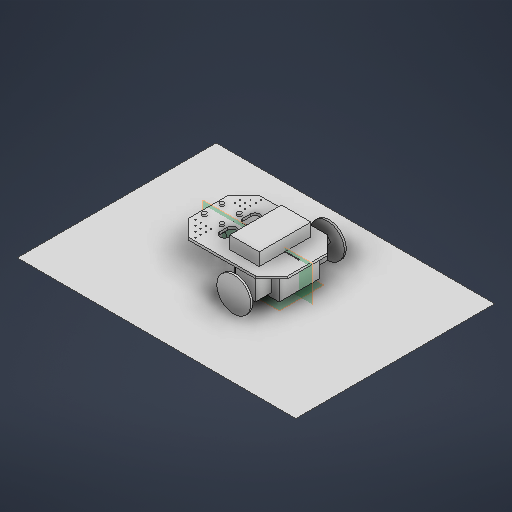
# Autodesk Inventor part: Part1
Saved by Autodesk Inventor 2027.1 (Build 311270010, 270A)
## iProperties
Created: 2026-10-01
Part Number: Part1
Material: Generic
Document SubType Name: Modeling
Designer: valde
Density: 1 g/cm^3
Appearance: Default
Author: valde
Autodesk Inventor part; units mm, degrees
ref_plane "YZ Plane" through (0, 0, 0) normal (1, 0, 0) x (0, 1, 0)
ref_plane "XZ Plane" through (0, 0, 0) normal (0, 1, 0) x (-1, 0, 0)
ref_plane "XY Plane" through (0, 0, 0) normal (0, 0, 1) x (1, 0, 0)
sketch "Sketch1" plane through (0, 0, 0) normal (0, 1, 0) x (-1, 0, 0)
  line L0 (0, 0) -> (-250, 0)
  line L1 (-250, 0) -> (-250, -180)
  line L2 (-250, -180) -> (0, -180)
  line L3 (0, -180) -> (0, 0)
  line L4 (0, -180) -> (0, -140)
  line L5 (0, -180) -> (-40, -180)
  line L6 (-40, -180) -> (0, -140)
  line L7 (0, 0) -> (0, -40)
  line L8 (0, -40) -> (-40, 0)
  line L9 (0, 0) -> (-40, 0)
  line L10 (-125, -180) -> (-125, 0)
  line L11 (0, 0) -> (0, -40)
  line L12 (-40, 0) -> (0, 0)
  line L13 (-210, -180) -> (-250, -140)
  line L14 (-250, -40) -> (-210, 0)
  dimension "d0" = 250
  dimension "d1" = 180
  dimension "d2" = 40
  dimension "d3" = 40
  dimension "d4" = 40
  constraints: 30 end point, 4 point on line, 4 symmetric about line, 3 perpendicular, 2 collinear, 2 midpoint, 2 parallel, 1 horizontal
  measures "d0" distance of L2.end L1.end
  measures "d1" distance of L1.end L0.end
  measures "d2" distance of L2.end L4.end
  measures "d3" distance of L2.end L5.end
  measures "d4" distance of L0.start L7.end
extrude "Extrusion1" add sketch "Sketch1" along normal blind 6 contours L8 L3 L6 L2 L10 L0 | L10 L2 L13 L1 L14 L0
sketch "Sketch8" plane through (0, 0, 0) normal (0, -1, 0) x (1, 0, 0)
  line L0 (250, -40) -> (250, -140) projected
  line L1 (210, 0) -> (250, -40) projected
  line L2 (164, -39) -> (160, -39) projected
  line L3 (210, 0) -> (160, 0)
  line L4 (160, 0) -> (160, -39)
  line L5 (160, -39) -> (210, -39)
  line L6 (210, -39) -> (210, 0)
  line L7 (250, -90) -> (0, -90)
  line L8 (0, -140) -> (0, -40) projected
  line L9 (164, -141) -> (160, -141)
  line L10 (210, -180) -> (160, -180)
  line L11 (160, -180) -> (160, -141)
  line L12 (160, -141) -> (210, -141)
  line L13 (210, -141) -> (210, -180)
  point P0 (0, 0)
  constraints: 20 end point, 5 symmetric about line, 2 midpoint, 2 parallel, 1 horizontal, 1 perpendicular
extrude "Extrusion7" add sketch "Sketch8" along normal blind 50 separate body
sketch "Sketch9" plane through (160, 0, 0) normal (0, 0, 1) x (1, 0, 0)
  line L0 (50, 0) -> (-120, 0) projected
  line L1 (0, 0) -> (0, -50) projected
  line L2 (50, 0) -> (0, 0)
  line L3 (0, 0) -> (25, 0)
  line L4 (25, 0) -> (25, -24)
  line L5 (25, 0) -> (49, 0) construction
  line L6 (25, -24) -> (25, -39)
  circle A0 centre (25, -31.5) radius 7.5
  point P0 (-160, 0)
  dimension "d39" = 24
  dimension "d40" = 90
  dimension "d41" = 15
  constraints: 10 end point, 3 perpendicular, 2 midpoint, 1 horizontal, 1 vertical, 1 vertical alignment, 2 other
  measures "d39" distance of L3.end L4.end
  measures "d40" angle of L4 L5
  measures "d41" distance of L4.end L6.end
extrude "Extrusion8" add sketch "Sketch9" along normal blind 30 separate body
sketch "Sketch10" plane through (185, -31.5, 30) normal (0, 0, 1) x (1, 0, 0)
  circle A0 centre (0, 0) radius 42.5
  point P0 (-185, 31.5)
  dimension "d44" = 85
  constraints: 1 centre point
  measures "d44" diameter of A0
extrude "Extrusion9" add sketch "Sketch10" against normal blind 5 bodies 3
sketch "Sketch11" plane through (0, 6, 0) normal (0, 1, 0) x (1, 0, 0)
  line L0 (250, 40) -> (250, 140) projected
  line L1 (250, 90) -> (229, 90)
  line L2 (229, 90) -> (144, 90)
  circle A0 centre (229, 90) radius 1
  circle A1 centre (144, 90) radius 1
  line L3 (144, 89) -> (229, 89)
  line L4 (229, 91) -> (144, 91)
  line L5 (229, 90) -> (189, 90)
  line L6 (229, 90) -> (269, 90) construction
  line L7 (189, 90) -> (189, 100)
  line L8 (189, 100) -> (104, 100)
  circle A2 centre (104, 100) radius 1
  circle A3 centre (189, 100) radius 1
  line L9 (189, 99) -> (104, 99)
  line L10 (104, 101) -> (189, 101)
  line L11 (189, 90) -> (189, 80)
  line L12 (189, 80) -> (104, 80)
  circle A4 centre (104, 80) radius 1
  circle A5 centre (189, 80) radius 1
  line L13 (189, 81) -> (104, 81)
  line L14 (104, 79) -> (189, 79)
  line L15 (0, 140) -> (0, 40) projected
  line L16 (0, 51.6193) -> (80, 51.6193)
  line L17 (0, 51.6193) -> (80, 51.6193) construction
  line L18 (40, 0) -> (210, 0) projected
  line L19 (80, 0) -> (80, 40)
  line L20 (80, 0) -> (120, 0) construction
  circle A6 centre (80, 51.6193) radius 11.6193
  line L21 (80, 40) -> (80, 82)
  line L22 (80, 82) -> (80, 70.381)
  circle A7 centre (80, 70.381) radius 11.619
  line L23 (68.3807, 51.6193) -> (68.381, 70.3812)
  line L24 (91.6193, 51.6193) -> (91.619, 70.3812)
  circle A8 centre (80, 128.3807) radius 11.6193
  circle A9 centre (80, 109.619) radius 11.619
  line L25 (68.3807, 128.3807) -> (68.381, 109.6188)
  line L26 (91.6193, 128.3807) -> (91.619, 109.6188)
  point P0 (0, 0)
  point P1 (91.619, 109.619)
  point P2 (91.619, 70.381)
  dimension "d47" = 21
  dimension "d48" = 85
  dimension "d49" = 2
  dimension "d50" = 2
  dimension "d51" = 40
  dimension "d52" = 180
  dimension "d53" = 10
  dimension "d54" = 85
  dimension "d55" = 90
  dimension "d56" = 2
  dimension "d57" = 2
  dimension "d58" = 80
  dimension "d59" = 0
  dimension "d60" = 40
  dimension "d61" = 90
  dimension "d62" = 42
  dimension "d63" = 11.619
  constraints: 48 end point, 24 point on circle, 15 symmetric about line, 10 centre point, 8 coincident, 7 point on line, 7 tangent, 4 horizontal, 4 perpendicular, 3 equal length, 1 collinear, 1 midpoint, 1 vertical, 4 other
  measures "d47" distance of L1.start L1.end
  measures "d48" distance of L1.end L2.end
  measures "d49" diameter of A0
  measures "d50" diameter of A1
  measures "d51" distance of L5.start L5.end
  measures "d52" angle of L5 L6
  measures "d53" distance of L5.end L7.end
  measures "d54" distance of L7.end L8.end
  measures "d55" angle of L8 L7
  measures "d56" diameter of A2
  measures "d57" diameter of A3
  measures "d58" distance of L16.start L16.end
  measures "d59" distance between parallel lines of L16 L17
  measures "d60" distance of L19.start L19.end
  measures "d61" angle of L20 L19
  measures "d62" distance of L19.end L21.end
  measures "d63" distance of L21.end L22.end
extrude "Extrusion10" cut sketch "Sketch11" against normal through all bodies 1
ref_plane "Work Plane4" through (210, 0, -90) normal (0, 0, -1) x (-1, 0, 0)
mirror "Mirror1" about plane through (210, 0, -90) normal (0, 0, -1) bodies 3
sketch "Sketch12" plane through (0, 6, 0) normal (0, 1, 0) x (1, 0, 0)
  line L0 (0, 140) -> (0, 40) projected
  line L1 (0, 65.2105) -> (13, 65.2105)
  line L2 (13, 65.2105) -> (13, 99.2105)
  circle A0 centre (13, 90) radius 17
  line L3 (13, 73) -> (13, 68)
  circle A1 centre (13, 68) radius 5
  line L4 (13, 107) -> (13, 112)
  circle A2 centre (13, 112) radius 5
  line L5 (18, 112) -> (57, 112)
  line L6 (18, 112) -> (57, 112) construction
  circle A3 centre (57, 112) radius 5
  line L7 (18, 68) -> (57, 68)
  circle A4 centre (57, 68) radius 5
  point P0 (0, 0)
  dimension "d66" = 13
  dimension "d67" = 34
  dimension "d68" = 34
  dimension "d76" = 5
  dimension "d77" = 5
  dimension "d78" = 39
  dimension "d79" = 0
  dimension "d80" = 10
  dimension "d81" = 39
  dimension "d82" = 10
  constraints: 14 end point, 4 centre point, 4 coincident, 4 horizontal, 4 point on circle, 4 point on line, 1 collinear, 1 horizontal alignment, 1 perpendicular, 1 vertical, 3 other
  measures "d66" distance of L1.start L1.end
  measures "d67" distance of L1.end L2.end
  measures "d68" diameter of A0
  measures "d76" distance of L3.start L3.end
  measures "d77" distance of L4.start L4.end
  measures "d78" distance of L5.start L5.end
  measures "d79" distance between parallel lines of L5 L6
  measures "d80" diameter of A3
  measures "d81" distance of L7.start L7.end
  measures "d82" diameter of A4
extrude "Extrusion11" add sketch "Sketch12" along normal blind 5 contours A3 | A2 | A4 | A1 L1 L2 | L2 L1 A1 bodies 1
sketch "Sketch13" plane through (0, 0, 0) normal (0, -1, 0) x (1, 0, 0)
  circle A0 centre (13, -112) radius 5 projected
  line L0 (18, -112) -> (52, -112)
  circle A1 centre (57, -112) radius 5 projected
  circle A2 centre (13, -68) radius 5 projected
  line L1 (18, -68) -> (52, -68)
  circle A3 centre (57, -68) radius 5 projected
  line L2 (35, -112) -> (35, -68)
  line L3 (35, -90) -> (35, -120)
  line L4 (35, -90) -> (5, -90)
  line L5 (35, -90) -> (35, -60)
  line L6 (35, -90) -> (65, -90)
  line L7 (5, -90) -> (5, -60)
  line L8 (5, -60) -> (65, -60)
  line L9 (65, -60) -> (65, -120)
  line L10 (65, -120) -> (5, -120)
  line L11 (5, -120) -> (5, -60)
  line L12 (5, -60) -> (65, -60)
  line L13 (65, -60) -> (65, -120)
  line L14 (65, -120) -> (5, -120)
  line L15 (5, -120) -> (5, -60)
  circle A4 centre (13, -112) radius 5
  circle A5 centre (13, -68) radius 5
  circle A6 centre (57, -68) radius 5
  circle A7 centre (57, -112) radius 5
  circle A8 centre (35, -90) radius 21
  point P0 (0, 0)
  dimension "d85" = 30
  dimension "d86" = 30
  dimension "d87" = 30
  dimension "d88" = 30
  dimension "d89" = 42
  constraints: 32 end point, 6 perpendicular, 5 centre point, 5 coincident, 4 horizontal alignment, 3 horizontal, 3 midpoint, 3 parallel, 2 point on line, 2 vertical, 8 other
  measures "d85" distance of L3.start L3.end
  measures "d86" distance of L3.start L4.end
  measures "d87" distance of L3.start L5.end
  measures "d88" distance of L3.start L6.end
  measures "d89" diameter of A8
extrude "Extrusion12" add sketch "Sketch13" along normal blind 2 separate body contours L3 L10 L11 L4 A8 L2 | L2 A8 L6 L9 L10 L3 | L4 L7 L8 L5 L2 A8 | A8 L2 L5 L8 L9 L6
extrude "Extrusion13" add sketch "Sketch13" along normal blind 40 contours A8 L4 L2 | L2 L6 A8 | L4 A8 L2 | L2 A8 L6 bodies 4
extrude "Extrusion14" add sketch "Sketch13" along normal blind 8 contours A0 | A1 | A2 | A3 bodies 1
sketch "Sketch14" plane through (210, 0, -90) normal (0, 0, -1) x (-1, 0, 0)
  line L0 (154, -2) -> (154, -40) projected
  line L1 (154, -40) -> (154, -8)
  line L2 (148, -8) -> (158, -8) projected
  line L3 (148, -8) -> (158, -8)
  line L4 (158, -8) -> (154, -8)
  line L5 (195.7274, -40) -> (154, -40)
  line L6 (196, -2) -> (196, -40) projected
  line L7 (196, -8) -> (196, -47)
  line L8 (154, -8) -> (196, -47)
  line L9 (196, -47) -> (154, -47)
  line L10 (154, -47) -> (154, -8)
  line L11 (196, -8) -> (196, -18)
  line L12 (192, -8) -> (202, -8) projected
  line L13 (145, -2) -> (205, -2) projected
  circle A0 centre (196, -47) radius 22.5
  line L14 (196, -18) -> (195.7385, -20.9886)
  line L15 (196, -18) -> (199, -18) construction
  line L16 (196, -21.0354) -> (218.5045, -24.5007)
  line L17 (218.5045, -24.5007) -> (218.9611, -21.5357)
  line L18 (218.9611, -21.5357) -> (196, -18)
  line L19 (218.9611, -21.5357) -> (233.45, -17.6534)
  line L20 (218.9611, -21.5357) -> (233.9611, -21.5357) construction
  line L21 (233.45, -17.6534) -> (233.9676, -19.5852)
  line L22 (233.9676, -19.5852) -> (218.7328, -23.0182)
  point P0 (210, 0)
  point P1 (179.5121, -31.6899)
  point P2 (188.4615, -40)
  point P3 (174.6166, -40)
  dimension "d96" = 39
  dimension "d98" = 10
  dimension "d99" = 6
  dimension "d100" = 45
  dimension "d101" = 3
  dimension "d102" = 95
  dimension "d103" = 3
  dimension "d104" = 15
  dimension "d105" = 15
  dimension "d106" = 2
  constraints: 36 end point, 6 point on line, 4 perpendicular, 3 collinear, 3 horizontal, 2 equal length, 1 centre point, 1 coincident, 1 midpoint, 1 parallel
  measures "d96" distance of L7.start L7.end
  measures "d98" distance of L7.start L11.end
  measures "d99" distance between parallel lines of L12 L13
  measures "d100" diameter of A0
  measures "d101" distance of L11.end L14.end
  measures "d102" angle of L14 L15
  measures "d103" distance of L16.end L17.end
  measures "d104" distance of L17.end L19.end
  measures "d105" angle of L20 L19
  measures "d106" distance of L19.end L21.end
extrude "Extrusion15" add sketch "Sketch14" along normal mid plane 25 contours L18 L17 L16 L6 | L19 L21 L22 L17 bodies 4
extrude "Extrusion16" add sketch "Sketch14" along normal mid plane 20 contours A0 L6 L7 L8 | L5 L8 L9 A0 | A0 L9 L7 L6 bodies 4
sketch "Sketch15" plane through (5, 0, -60) normal (0, 0, 1) x (1, 0, 0)
  arc A0 (11.5338, -24.6431) -> (30.3834, -40) centre (9, -47) ccw projected
  line L0 (-13.5, -47) -> (31.5, -47)
  line L1 (9, -47) -> (51, -2)
  line L2 (51, -2) -> (51, -40) projected
  line L3 (51, -47) -> (9, -47)
  line L4 (51, -47) -> (51, -2)
  line L5 (0, -2) -> (60, -2) projected
  point P0 (-5, 0)
  constraints: 8 end point, 2 point on circle, 2 point on line, 1 collinear, 1 horizontal, 1 perpendicular
extrude "Extrusion17" cut sketch "Sketch15" along normal mid plane 108.75 contours L0 L1 L2 L4 L3 bodies 4
sketch "Sketch16" plane through (210, 0, -80) normal (0, 0, 1) x (1, 0, 0)
  line L0 (-196, -47) -> (-173.5, -47) projected
  circle A0 centre (-196, -47) radius 22.5
  point P0 (-210, 0)
  constraints: 1 horizontal alignment, 2 other
extrude "Extrusion18" add sketch "Sketch16" against normal blind 20 bodies 4
sketch "Sketch17" plane through (0, 6, 0) normal (0, 1, 0) x (1, 0, 0)
  line L0 (250, 40) -> (250, 140) projected
  line L1 (250, 90) -> (194, 90)
  line L2 (144, 91) -> (229, 91) projected
  line L3 (250, 90) -> (306, 90) construction
  line L4 (194, 90) -> (194, 155)
  line L5 (144, 89) -> (229, 89) projected
  line L6 (194, 90) -> (259, 90) construction
  line L7 (194, 155) -> (194, 25)
  line L8 (194, 25) -> (120, 25)
  line L9 (120, 25) -> (120, 155)
  line L10 (120, 155) -> (194, 155)
  line L11 (160, 141) -> (160, 180) projected
  point P0 (0, 0)
  dimension "d115" = 56
  dimension "d116" = 180
  dimension "d117" = 65
  dimension "d118" = 90
  dimension "d119" = 130
  dimension "d120" = 74
  constraints: 16 end point, 4 perpendicular, 2 equal length, 2 horizontal, 1 midpoint, 1 parallel, 1 point on line
  measures "d115" distance of L1.start L1.end
  measures "d116" angle of L1 L3
  measures "d117" distance of L1.end L4.end
  measures "d118" angle of L6 L4
  measures "d119" distance of L4.end L7.end
  measures "d120" distance of L7.end L8.end
extrude "Extrusion19" add sketch "Sketch17" along normal blind 32 separate body
sketch "Sketch18" plane through (0, 0, 0) normal (0, -1, 0) x (1, 0, 0)
  line L0 (210, -39) -> (210, 0) projected
  line L1 (210, -39) -> (230, -39)
  line L2 (230, -39) -> (118, -39)
  line L3 (230, -39) -> (118, -39)
  line L4 (118, -39) -> (118, -141)
  line L5 (118, -141) -> (230, -141)
  line L6 (230, -141) -> (230, -39)
  point P0 (0, 0)
  dimension "d123" = 20
  dimension "d124" = 112
  dimension "d125" = 112
  dimension "d126" = 102
  constraints: 12 end point, 2 horizontal, 2 parallel, 1 perpendicular, 1 point on line
  measures "d123" distance of L0.start L1.end
  measures "d124" distance of L1.end L2.end
  measures "d125" distance of L5.end L4.end
  measures "d126" distance of L4.end L3.end
extrude "Extrusion20" add sketch "Sketch18" along normal blind 60 separate body
ref_plane "Work Plane5" through (0, -74, 0) normal (0, -1, 0) x (1, 0, 0)
sketch "Sketch19" plane through (0, -74, 0) normal (0, -1, 0) x (1, 0, 0)
  line L0 (490.711, -320.1565) -> (-209.289, -320.1565)
  line L1 (-209.289, -320.1565) -> (-209.289, 179.8435)
  line L2 (-209.289, 179.8435) -> (490.711, 179.8435)
  line L3 (490.711, 179.8435) -> (490.711, -320.1565)
  point P0 (0, 0)
  dimension "d130" = 700
  dimension "d131" = 500
  constraints: 8 end point, 2 parallel, 1 horizontal, 1 perpendicular
  measures "d130" distance of L1.end L2.end
  measures "d131" distance of L0.end L1.end
extrude "Extrusion21" add sketch "Sketch19" along normal blind 0.001 separate body
sketch "Sketch20" plane through (0, 6, 0) normal (0, 1, 0) x (1, 0, 0)
  line L0 (0, 140) -> (0, 40) projected
  line L1 (0, 45.7353) -> (12, 45.7353)
  line L2 (0, 45.7353) -> (12, 45.7353) construction
  line L3 (0, 40) -> (0, 47)
  line L4 (0, 47) -> (12, 47)
  circle A0 centre (12, 47) radius 1.5
  line L5 (13.5, 47) -> (23.5, 47)
  line L6 (23.5, 47) -> (25, 47)
  circle A1 centre (25, 47) radius 1.5
  line L7 (26.5, 47) -> (38, 47)
  line L8 (26.5, 47) -> (38, 47) construction
  circle A2 centre (38, 47) radius 1.5
  line L9 (25, 45.5) -> (25, 34)
  line L10 (25, 45.5) -> (36.5, 45.5) construction
  circle A3 centre (25, 34) radius 1.5
  line L11 (39.5, 47) -> (51, 47)
  circle A4 centre (51, 47) radius 1.5
  line L12 (51, 45.5) -> (51, 34)
  line L13 (51, 45.5) -> (62.5, 45.5) construction
  circle A5 centre (51, 34) radius 1.5
  line L14 (38, 45.5) -> (38, 34)
  line L15 (38, 45.5) -> (49.5, 45.5) construction
  circle A6 centre (38, 34) radius 1.5
  line L16 (38, 32.5) -> (38, 21)
  line L17 (38, 32.5) -> (49.5, 32.5) construction
  circle A7 centre (38, 21) radius 1.5
  line L18 (39.5, 21) -> (51, 21)
  line L19 (39.5, 21) -> (51, 21) construction
  circle A8 centre (51, 21) radius 1.5
  line L20 (51, 19.5) -> (51, 8)
  circle A9 centre (51, 8) radius 1.5
  line L21 (52.5, 90) -> (36.5, 90)
  line L22 (36.5, 80) -> (36.5, 100) projected
  circle A10 centre (12, 133) radius 1.5
  circle A11 centre (25, 133) radius 1.5
  circle A12 centre (38, 133) radius 1.5
  circle A13 centre (25, 146) radius 1.5
  circle A14 centre (51, 133) radius 1.5
  circle A15 centre (51, 146) radius 1.5
  circle A16 centre (38, 146) radius 1.5
  circle A17 centre (38, 159) radius 1.5
  circle A18 centre (51, 159) radius 1.5
  circle A19 centre (51, 172) radius 1.5
  point P0 (0, 0)
  dimension "d137" = 3
  dimension "d148" = 3
  dimension "d155" = 3
  dimension "d158" = 3
  dimension "d134" = 12
  dimension "d135" = 0
  dimension "d136" = 7
  dimension "d138" = 10
  dimension "d141" = 1.5
  dimension "d142" = 11.5
  dimension "d143" = 0
  dimension "d144" = 11.5
  dimension "d145" = 90
  dimension "d146" = 3
  dimension "d147" = 11.5
  dimension "d149" = 11.5
  dimension "d150" = 90
  dimension "d151" = 11.5
  dimension "d152" = 90
  dimension "d153" = 11.5
  dimension "d154" = 90
  dimension "d156" = 11.5
  dimension "d157" = 0
  dimension "d159" = 11.5
  dimension "d160" = 3
  constraints: 42 end point, 15 centre point, 11 horizontal, 10 coincident, 10 symmetric about line, 9 equal length, 5 point on circle, 3 perpendicular, 3 point on line, 3 vertical alignment, 2 horizontal alignment, 2 vertical, 1 midpoint, 20 other
  measures "d134" distance of L1.start L1.end
  measures "d135" distance between parallel lines of L1 L2
  measures "d136" distance of L0.end L3.end
  measures "d138" distance of L5.start L5.end
  measures "d141" distance of L5.end L6.end
  measures "d142" distance of L7.start L7.end
  measures "d143" distance between parallel lines of L7 L8
  measures "d144" distance of L9.start L9.end
  measures "d145" angle of L9 L10
  measures "d146" diameter of A3
  measures "d147" distance of L11.start L11.end
  measures "d149" distance of L12.start L12.end
  measures "d150" angle of L12 L13
  measures "d151" distance of L14.start L14.end
  measures "d152" angle of L14 L15
  measures "d153" distance of L16.start L16.end
  measures "d154" angle of L16 L17
  measures "d156" distance of L18.start L18.end
  measures "d157" distance between parallel lines of L18 L19
  measures "d159" distance of L20.start L20.end
  measures "d160" diameter of A9
extrude "Extrusion22" cut sketch "Sketch20" against normal blind 6 contours A5 | A4 | A9 | A8 | A7 | A6 | A2 | A3 | A1 | A0 | A11 | A12 | A13 | A14 | A15 | A16 | A17 | A18 | A19 bodies 1
body "Solid1"
body "Solid6"
body "Solid7"
